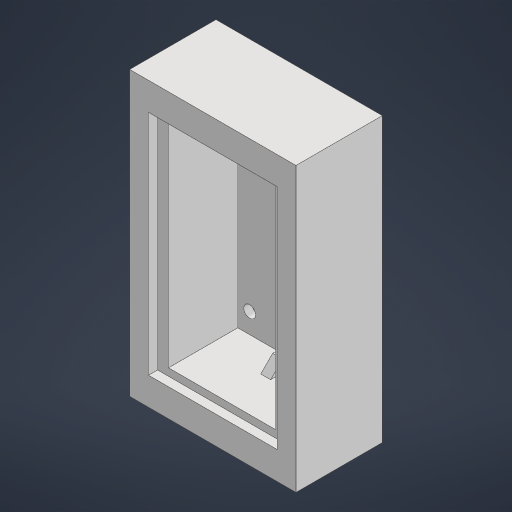
# Autodesk Inventor part: NEGATIVE
Saved by Autodesk Inventor 2024.3 (Build 283343000, 343)
## iProperties
Created: 2026-06-26
Part Number: NEGATIVE
Material: Generic
Document SubType Name: Modeling
Designer: REMOTE
Density: 1 g/cm^3
Appearance: Default
Author: REMOTE
Autodesk Inventor part; units mm, degrees
ref_plane "YZ Plane" through (0, 0, 0) normal (1, 0, 0) x (0, 1, 0)
ref_plane "XZ Plane" through (0, 0, 0) normal (0, 1, 0) x (-1, 0, 0)
ref_plane "XY Plane" through (0, 0, 0) normal (0, 0, 1) x (1, 0, 0)
sketch "Sketch1" plane through (0, 0, 0) normal (0, 0, 1) x (1, 0, 0)
  line L0 (-21, -35.75) -> (21, -35.75)
  line L1 (21, -35.75) -> (21, 35.75)
  line L2 (21, 35.75) -> (-21, 35.75)
  line L3 (-21, 35.75) -> (-21, -35.75)
  line L4 (-21, -35.75) -> (21, 35.75) construction
  line L5 (21, -35.75) -> (-21, 35.75) construction
  point P0 (0, 0)
  dimension "d0" = 42
  dimension "d1" = 71.5
  constraints: 12 end point, 2 midpoint, 2 parallel, 1 horizontal, 1 perpendicular
  measures "d0" distance of L2.end L1.end
  measures "d1" distance of L1.end L0.end
extrude "Extrusion1" add sketch "Sketch1" along normal blind 29
sketch "Sketch2" plane through (0, 0, 29) normal (0, 0, 1) x (1, 0, 0)
  line L0 (-16.25, -28.75) -> (16.25, -28.75)
  line L1 (16.25, -28.75) -> (16.25, 28.75)
  line L2 (16.25, 28.75) -> (-16.25, 28.75)
  line L3 (-16.25, 28.75) -> (-16.25, -28.75)
  line L4 (-16.25, -28.75) -> (16.25, 28.75) construction
  line L5 (16.25, -28.75) -> (-16.25, 28.75) construction
  point P0 (0, 0)
  dimension "d4" = 32.5
  dimension "d5" = 57.5
  constraints: 12 end point, 2 midpoint, 2 parallel, 1 horizontal, 1 perpendicular
  measures "d4" distance of L2.end L1.end
  measures "d5" distance of L1.end L0.end
extrude "Extrusion2" cut sketch "Sketch2" against normal blind 2.3
sketch "Sketch3" plane through (0, 0, 26.7) normal (0, 0, 1) x (1, 0, 0)
  line L0 (13.5, -26.9) -> (-13.5, -26.9)
  line L1 (-13.5, -26.9) -> (-13.5, 26.9)
  line L2 (-13.5, 26.9) -> (13.5, 26.9)
  line L3 (13.5, 26.9) -> (13.5, -26.9)
  line L4 (13.5, -26.9) -> (-13.5, 26.9) construction
  line L5 (-13.5, -26.9) -> (13.5, 26.9) construction
  point P0 (0, 0)
  dimension "d8" = 27
  dimension "d9" = 53.8
  constraints: 12 end point, 2 midpoint, 2 parallel, 1 horizontal, 1 perpendicular
  measures "d8" distance of L1.end L2.end
  measures "d9" distance of L0.end L1.end
extrude "Extrusion3" cut sketch "Sketch3" against normal blind 17.5
sketch "Sketch4" plane through (0, 0, 9.2) normal (0, 0, 1) x (1, 0, 0)
  line L0 (-13.5, 26.9) -> (13.5, 26.9) projected
  line L1 (-13.5, -26.9) -> (-13.5, 26.9) projected
  line L2 (13.5, -26.9) -> (-13.5, -26.9) projected
  line L3 (13.5, 26.9) -> (13.5, -26.9) projected
  circle A0 centre (-10.5, -21.825) radius 1.5
  circle A1 centre (-10.5, 21.825) radius 1.5
  point P0 (0, 0)
  dimension "d12" = 3
  dimension "d13" = 3
  dimension "d14" = 3
  dimension "d15" = 3
  dimension "d16" = 43.65
  dimension "d17" = 5.075
  constraints: 2 centre point
  measures "d12" diameter of A0
  measures "d13" diameter of A1
  measures "d14" distance from line of L1 A0.centre
  measures "d15" distance from line of L1 A1.centre
  measures "d16" distance of A1.centre A0.centre
  measures "d17" distance from line of L2 A0.centre
extrude "Extrusion4" cut sketch "Sketch4" against normal up to surface (9.2 mm away) contours A0 | A1
sketch "Sketch5" plane through (0, 0, 0) normal (0, 0, -1) x (-1, 0, 0)
  circle A0 centre (10.5, -21.825) radius 1.5 projected
  circle A1 centre (10.5, 21.825) radius 1.5 projected
  line L0 (-21, -35.75) -> (-21, 35.75) projected
  line L1 (21, -35.75) -> (-21, -35.75) projected
  line L2 (21, 35.75) -> (21, -35.75) projected
  line L3 (-21, 35.75) -> (21, 35.75) projected
  point P0 (0, 0)
extrude "Extrusion5" cut sketch "Sketch5" against normal blind 7.2
sketch "Sketch6" plane through (0, 0, 9.2) normal (0, 0, 1) x (1, 0, 0)
  line L0 (-13.5, -26.9) -> (-13.5, 26.9) projected
  line L1 (-0.5, -26.9) -> (-0.5, 26.9) construction
  line L2 (2, -26.9) -> (2, 26.9) construction
  line L3 (-0.5, 26.9) -> (2, 26.9)
  line L4 (2, 26.9) -> (2, 23.9)
  line L5 (2, 23.9) -> (-0.5, 23.9)
  line L6 (-0.5, 23.9) -> (-0.5, 26.9)
  line L7 (-0.5, -26.9) -> (2, -26.9)
  line L8 (2, -26.9) -> (2, -23.9)
  line L9 (2, -23.9) -> (-0.5, -23.9)
  line L10 (-0.5, -23.9) -> (-0.5, -26.9)
  point P0 (0, 0)
  dimension "d22" = 13
  dimension "d23" = 2.5
  dimension "d24" = 3
  dimension "d25" = 3
  constraints: 20 end point, 6 parallel, 2 horizontal, 2 perpendicular, 2 point on line
  measures "d22" distance between parallel lines of L0 L1
  measures "d23" distance between parallel lines of L1 L2
  measures "d24" distance of L3.end L4.end
  measures "d25" distance of L8.end L7.end
extrude "Extrusion6" add sketch "Sketch6" along normal blind 7.2
chamfer "Chamfer1" distance 3 angle 45 2 edges at (0.75, -23.9, 16.4) (0.75, 23.9, 16.4)
body "Solid1"
